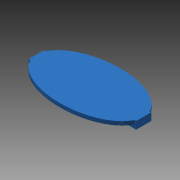
# Autodesk Inventor part: body_bank
Saved by Autodesk Inventor 2014 (Build 180170000, 170)
## iProperties
Created: 2014-09-19
Part Number: body_bank
Material: Všeobecné
Document SubType Name: Modeling
Designer: brodhaq
Density: 1 g/cm^3
Appearance: Výchozí
Author: brodhaq
Autodesk Inventor part; units mm, degrees
ref_plane "YZ Plane" through (0, 0, 0) normal (1, 0, 0) x (0, 1, 0)
ref_plane "XZ Plane" through (0, 0, 0) normal (0, 1, 0) x (-1, 0, 0)
ref_plane "XY Plane" through (0, 0, 0) normal (0, 0, 1) x (1, 0, 0)
sketch "Náčrt1" plane through (0, 0, 0) normal (0, 0, 1) x (1, 0, 0)
  ellipse E0 centre (0, 0) end of major axis (28.5, 0) minor radius 16
  line L0 (-28.5, 0) -> (28.5, 0)
  line L1 (28.5, 0) -> (28.5, 4)
  line L2 (28.5, 4) -> (-28.5, 4)
  line L3 (-28.5, 4) -> (-28.5, 0)
  line L4 (-28.5, 0) -> (28.5, 0)
  line L5 (28.5, 0) -> (28.5, -4)
  line L6 (28.5, -4) -> (-28.5, -4)
  line L7 (-28.5, -4) -> (-28.5, 0)
  dimension "d0" = 28.5
  dimension "d1" = 16
  dimension "d2" = 4
  dimension "d3" = 4
  dimension "d8" = 28.5
  dimension "d9" = 28.5
  constraints: 16 end point, 4 parallel, 2 horizontal, 2 perpendicular, 1 coincident, 1 horizontal alignment, 2 other
  measures "d2" distance of L0.end L1.end
  measures "d3" distance of L4.end L5.end
  measures "d8" distance from line of L1 point (0, 0)
  measures "d9" distance from line of L5 point (0, 0)
extrude "Vysunutí1" add sketch "Náčrt1" along normal blind 2
extrude "Vysunutí2" add sketch "Náčrt1" against normal blind 2 separate body contours L0 E0 L2 | L5 L6 E0 | E0 L6 L0 | E0 L2 L1 | L3 L2 E0 | E0 L6 L7
